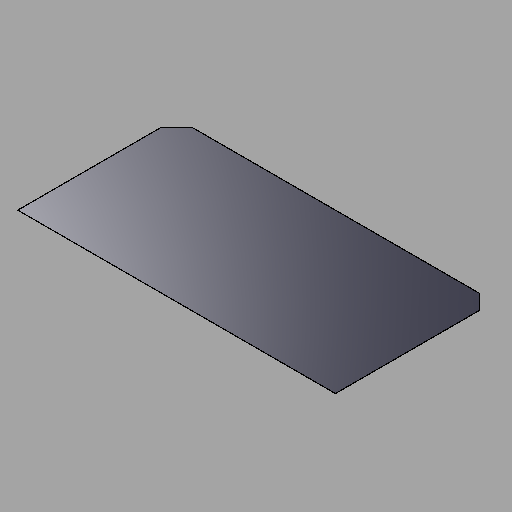
# Autodesk Inventor part: Half_Cut_Cell
Saved by Autodesk Inventor 2026.2 (Build 302298000, 298)
## iProperties
Created: 2026-11-08
Part Number: Half_Cut_Cell
Material: Generic
Document SubType Name: Modeling
Designer: Jacob
Density: 1 g/cm^3
Appearance: Satin - Midnight Blue
Author: Jacob
Cell_Width: 182.200 mm
Cell_Length: 91.100 mm
Cell_Thickness: 0.165 mm
Cell_Chamfer: 8.690 mm
Autodesk Inventor part; units mm, degrees
ref_plane "YZ Plane" through (0, 0, 0) normal (1, 0, 0) x (0, 1, 0)
ref_plane "XZ Plane" through (0, 0, 0) normal (0, 1, 0) x (-1, 0, 0)
ref_plane "XY Plane" through (0, 0, 0) normal (0, 0, 1) x (1, 0, 0)
sketch "Sketch1" plane through (0, 0, 0) normal (0, 1, 0) x (-1, 0, 0)
  line L0 (0, -63.77) -> (0, 63.77) construction
  line L1 (-91.1, 45.55) -> (91.1, 45.55)
  line L2 (91.1, 45.55) -> (91.1, -36.86)
  line L3 (91.1, -36.86) -> (82.41, -45.55)
  line L4 (82.41, -45.55) -> (-82.41, -45.55)
  line L5 (-82.41, -45.55) -> (-91.1, -36.86)
  line L6 (-91.1, -36.86) -> (-91.1, 45.55)
  point P0 (0, 0)
  dimension "d0" = 182.2
  dimension "d1" = 45.55
  dimension "d2" = 45.55
  dimension "d3" = 8.69
  dimension "d4" = 8.69
  constraints: 12 end point, 2 horizontal, 2 vertical, 2 other
  measures "d0" distance of L1.start L1.end
  measures "d1" vertical distance of point (0, 0) L1.start
  measures "d2" vertical distance of point (0, 0) L3.end
  measures "d3" horizontal distance of L3.end L2.end
  measures "d4" horizontal distance of L2.end L3.end
extrude "Extrusion1" add sketch "Sketch1" along normal blind 0.165
equation "\"d0\" = Cell_Width"
equation "\"d1\" = 0.5 * Cell_Length"
equation "\"d2\" = 0.5 * Cell_Length"
equation "\"d3\" = Cell_Chamfer"
equation "\"d4\" = Cell_Chamfer"
equation "\"d5\" = Cell_Thickness"
equation "\"Cell_Width\" = 182.2"
equation "\"Cell_Length\" = 91.1"
equation "\"Cell_Thickness\" = 0.165"
equation "\"Cell_Chamfer\" = 8.69"
body "Solid1"
